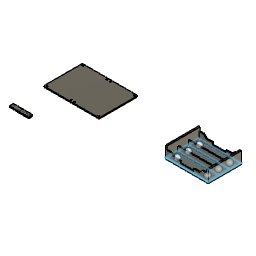
CellSyncLib (Autodesk Fusion 360 design; units mm, degrees)
Autodesk Fusion 360 part; units mm, degrees
sketch "Sketch1" plane through (0, 0, 0) normal (0, 0, 1) x (1, 0, 0)
  line L0 (-200.4, 100) -> (-100, 100)
  line L1 (-100, 100) -> (-100, 30)
  line L2 (-100, 30) -> (-200.4, 30)
  line L3 (-200.4, 30) -> (-200.4, 100)
  circle A0 centre (-197, 33) radius 1.5
  circle A1 centre (-197, 97.5) radius 1.5
  circle A2 centre (-153.5, 97.5) radius 1.5
  circle A3 centre (-153.5, 33) radius 1.5
  circle A4 centre (-147, 33) radius 1.5
  circle A5 centre (-147, 97.5) radius 1.5
  circle A6 centre (-103.5, 33) radius 1.5
  circle A7 centre (-103.5, 97.5) radius 1.5
  dimension "d1" = 100.4
  dimension "d2" = 70
  dimension "d3" = 3
  dimension "d4" = 3
  dimension "d5" = 3.4
  dimension "d6" = 3
  dimension "d7" = 3.4
  dimension "d8" = 64.5
  dimension "d9" = 3
  dimension "d10" = 3
  dimension "d11" = 64.5
  dimension "d12" = 3
  dimension "d13" = 3
  dimension "d14" = 64.5
  dimension "d15" = 3
  dimension "d16" = 3
  dimension "d17" = 64.5
  constraint horizontal L0
  constraint vertical L1
  constraint horizontal L2
  constraint vertical L3
  measures "d1" distance of L0.start L0.end
  measures "d2" distance of L0.start L2.end
  measures "d3" diameter of A0
  measures "d4" distance of L2 A0.centre
  measures "d5" distance of L3 A0.centre
  measures "d6" diameter of A1
  measures "d7" distance of L3 A1.centre
  measures "d8" distance of A0.centre A1.centre
  measures "d9" diameter of A3
  measures "d10" diameter of A2
  measures "d11" distance of A3.centre A2.centre
  measures "d12" diameter of A4
  measures "d13" diameter of A5
  measures "d14" distance of A4.centre A5.centre
  measures "d15" diameter of A6
  measures "d16" diameter of A7
  measures "d17" distance of A6.centre A7.centre
extrude "Extrude1" add sketch "Sketch1" along normal blind 1.6 makes body 1
sketch "Sketch2" plane through (0, 0, 0) normal (0, 0, 1) x (1, 0, 0)
  line L0 (-200, -25) -> (-165, -25)
  line L1 (-165, -25) -> (-165, -32.5)
  line L2 (-165, -32.5) -> (-200, -32.5)
  line L3 (-200, -32.5) -> (-200, -25)
  line L4 (-166, -26) -> (-169, -26)
  line L5 (-169, -26) -> (-169, -31)
  line L6 (-169, -31) -> (-166, -31)
  line L7 (-166, -31) -> (-166, -26)
  line L8 (-172.6, -26) -> (-172.6, -31)
  line L9 (-169.6, -26) -> (-172.6, -26)
  line L10 (-172.6, -31) -> (-169.6, -31)
  line L11 (-169.6, -31) -> (-169.6, -26)
  line L12 (-176.2, -26) -> (-176.2, -31)
  line L13 (-173.2, -26) -> (-176.2, -26)
  line L14 (-176.2, -31) -> (-173.2, -31)
  line L15 (-173.2, -31) -> (-173.2, -26)
  line L16 (-179.8, -26) -> (-179.8, -31)
  line L17 (-176.8, -26) -> (-179.8, -26)
  line L18 (-179.8, -31) -> (-176.8, -31)
  line L19 (-176.8, -31) -> (-176.8, -26)
  line L20 (-183.4, -26) -> (-183.4, -31)
  line L21 (-180.4, -26) -> (-183.4, -26)
  line L22 (-183.4, -31) -> (-180.4, -31)
  line L23 (-180.4, -31) -> (-180.4, -26)
  line L24 (-187, -26) -> (-187, -31)
  line L25 (-184, -26) -> (-187, -26)
  line L26 (-187, -31) -> (-184, -31)
  line L27 (-184, -31) -> (-184, -26)
  line L28 (-197, -27) -> (-195, -27)
  line L29 (-195, -27) -> (-195, -30)
  line L30 (-195, -30) -> (-197, -30)
  line L31 (-197, -30) -> (-197, -27)
  dimension "d20" = 35
  dimension "d21" = 7.5
  dimension "d24" = -18
  dimension "d25" = 0
  constraint horizontal L0
  constraint vertical L1
  constraint horizontal L2
  constraint vertical L3
  constraint horizontal L4
  constraint vertical L5
  constraint horizontal L6
  constraint vertical L7
  constraint horizontal L28
  constraint vertical L29
  constraint horizontal L30
  constraint vertical L31
  measures "d20" distance of L0.start L0.end
  measures "d21" distance of L0.start L2.end
extrude "Extrude2" add sketch "Sketch2" along normal blind 1.6 separate body contours L0 L1 L2 L3 | L4 L5 L6 L7 | L8 L9 L10 L11 | L12 L13 L14 L15 | L16 L17 L18 L19 | L20 L21 L22 L23 | L24 L25 L26 L27 | L28 L29 L30 L31 makes body 2
extrude "Extrude3" add sketch "Sketch2" against normal blind 2 contours L4 L5 L6 L7 | L8 L9 L10 L11 | L12 L13 L14 L15 | L16 L17 L18 L19 | L20 L21 L22 L23 | L24 L25 L26 L27 | L28 L29 L30 L31 bodies 2
sketch "Sketch3" plane through (0, 0, 0) normal (0, 0, 1) x (1, 0, 0)
  line L0 (20, 90) -> (97.4, 90)
  line L1 (97.4, 90) -> (97.4, 30)
  line L2 (97.4, 30) -> (20, 30)
  line L3 (20, 30) -> (20, 90)
  line L4 (94.7, 90) -> (94.7, 30)
  line L5 (22.7, 90) -> (22.7, 30)
  line L6 (22.7, 88.3) -> (94.7, 88.3)
  line L7 (22.7, 70.4) -> (94.7, 70.4)
  line L8 (22.7, 68.7) -> (94.7, 68.7)
  line L9 (22.7, 51.3) -> (94.7, 51.3)
  line L10 (22.7, 49.6) -> (94.7, 49.6)
  line L11 (22.7, 31.7) -> (94.7, 31.7)
  circle A0 centre (86.2, 80) radius 1.5
  circle A1 centre (86.2, 40) radius 1.5
  circle A2 centre (86.2, 60) radius 1.5
  circle A3 centre (31.2, 80) radius 1.5
  circle A4 centre (31.2, 60) radius 1.5
  circle A5 centre (31.2, 40) radius 1.5
  dimension "d30" = 77.4
  dimension "d31" = 60
  dimension "d32" = 2.7
  dimension "d33" = 2.7
  dimension "d34" = 1.7
  dimension "d35" = 17.9
  dimension "d36" = 1.7
  dimension "d37" = 1.7
  dimension "d38" = 17.9
  dimension "d39" = 1.7
  dimension "d57" = 3
  dimension "d58" = 11.2
  dimension "d59" = 10
  dimension "d60" = 3
  dimension "d61" = 11.2
  dimension "d62" = 10
  dimension "d63" = 3
  dimension "d64" = 11.2
  dimension "d65" = 3
  dimension "d66" = 3
  dimension "d67" = 3
  constraint horizontal L0
  constraint vertical L1
  constraint horizontal L2
  constraint vertical L3
  constraint coincident L0 L4.start
  constraint coincident L2 L4.end
  constraint perpendicular L0 L4
  constraint coincident L0 L5.start
  constraint coincident L2 L5.end
  constraint perpendicular L2 L5
  constraint perpendicular L1 L6
  constraint perpendicular L1 L7
  constraint perpendicular L1 L8
  constraint perpendicular L1 L9
  constraint perpendicular L1 L10
  constraint perpendicular L1 L11
  constraint coincident L5 L6.start
  constraint coincident L5 L7.start
  constraint coincident L5 L8.start
  constraint coincident L5 L9.start
  constraint coincident L5 L10.start
  constraint coincident L5 L11.start
  constraint coincident L4 L11.end
  constraint coincident L4 L10.end
  constraint coincident L4 L9.end
  constraint coincident L4 L8.end
  constraint coincident L4 L7.end
  constraint coincident L4 L6.end
  measures "d30" distance of L0.start L0.end
  measures "d31" distance of L0.start L2.end
  measures "d32" distance of L1 L4
  measures "d33" distance of L3 L5
  measures "d34" distance of L0 L6
  measures "d35" distance of L6 L7
  measures "d36" distance of L7 L8
  measures "d37" distance of L2 L11
  measures "d38" distance of L10 L11
  measures "d39" distance of L9 L10
  measures "d57" diameter of A0
  measures "d58" distance of L1 A0.centre
  measures "d59" distance of L0 A0.centre
  measures "d60" diameter of A1
  measures "d61" distance of L1 A1.centre
  measures "d62" distance of L2 A1.centre
  measures "d63" diameter of A2
  measures "d64" distance of L1 A2.centre
  measures "d65" diameter of A3
  measures "d66" diameter of A5
  measures "d67" diameter of A4
extrude "Extrude4" add sketch "Sketch3" against normal blind 2.5 separate body contours L0 L2 L3 L5 | L0 L4 L5 L6 | L0 L1 L2 L4 | L4 L5 L6 L7 | L2 L4 L5 L11 | L4 L5 L7 L8 | L4 L5 L10 L11 | L4 L5 L8 L9 | L4 L5 L9 L10 | A0 | A1 | A2 | A3 | A4 | A5 makes body 3
extrude "Extrude5" add sketch "Sketch3" along normal blind 19 contours L0 L2 L3 L5 | L0 L1 L2 L4 bodies 3
extrude "Extrude6" add sketch "Sketch3" against normal blind 2 contours L4 L5 L7 L8 | L4 L5 L9 L10 bodies 3
extrude "Extrude7" add sketch "Sketch3" along normal blind 12.5 contours L0 L4 L5 L6 | L2 L4 L5 L11 bodies 3
sketch "Sketch4" plane through (0, 30, 0) normal (0, -1, 0) x (1, 0, 0)
  line L0 (94.7, 12.5) -> (22.7, 12.5)
  line L1 (22.7, 12.5) -> (22.7, 19)
  line L2 (22.7, 19) -> (20, 19)
  line L3 (20, 19) -> (20, -2.5)
  line L4 (20, -2.5) -> (97.4, -2.5)
  line L5 (97.4, -2.5) -> (97.4, 19)
  line L6 (97.4, 19) -> (94.7, 19)
  line L7 (94.7, 19) -> (94.7, 12.5)
  line L8 (22.7, 12.5) -> (30.7, 12.5)
  line L9 (58.7, 12.5) -> (58.7, 25)
  line L10 (22.7, 12.5) -> (22.7, 5)
  line L11 (35.7, 7.5) -> (46.7, 7.5)
  line L12 (30.7, 12.5) -> (35.7, 7.5)
  line L13 (46.7, 7.5) -> (46.7, 3.5)
  line L14 (94.7, 12.5) -> (86.7, 12.5)
  line L15 (86.7, 12.5) -> (81.7, 7.5)
  line L16 (81.7, 7.5) -> (70.7, 7.5)
  line L17 (70.7, 7.5) -> (70.7, 3.5)
  line L18 (46.7, 3.5) -> (70.7, 3.5)
  line L19 (30.7, 12.5) -> (86.7, 12.5)
  point P0 (22.7, 12.5)
  point P1 (94.7, 12.5)
  dimension "d48" = 8
  dimension "d49" = 5
  dimension "d50" = 13
  dimension "d51" = 11
  dimension "d52" = 4
  constraint coincident P0 L0.end
  constraint perpendicular L1 L8
  constraint midpoint L0 L9.start
  constraint perpendicular L0 L9
  constraint perpendicular L0 L10
  constraint parallel L0 L11
  constraint perpendicular L11 L13
  constraint symmetric P0 L9 P1
  constraint symmetric L8.end L9 L14.end
  constraint symmetric L9 L11.start L15.end
  constraint symmetric L9 L11.end L16.end
  constraint symmetric L9 L13.end L17.end
  measures "d48" distance of P0 L8.end
  measures "d49" distance of L8 L11
  measures "d50" distance of L10 L11.start
  measures "d51" distance of L11.start L11.end
  measures "d52" distance of L11.end L13.end
extrude "Extrude8" cut sketch "Sketch4" against normal blind 64 contours L0 L11 L12 L13 L15 L16 L17 L18 L19 bodies 3
extrude "Extrude9" add sketch "Sketch3" along normal blind 9.2 separate body contours L4 L5 L7 L8 | L4 L5 L9 L10 makes body 4 at (46.7, 70.4, 6.1333) makes body 5 at (46.7, 51.3, 6.1333)
combine "Combine1" operation add target body 5 tool bodies 4 3
extrude "Extrude10" cut sketch "Sketch3" against normal blind 15 contours A0 | A1 | A2 | A3 | A4 | A5 bodies 5
copy_body "Body->Comp1" bodies 5 removing the originals makes body 6 in component "CellHolder1S3P"
copy_body "Body->Comp2" bodies 1 removing the originals makes body 7 in component "MainBoard"
copy_body "Body->Comp3" bodies 2 removing the originals makes body 8 in component "BMS1S"
component "CellHolder1S3P" placed x (1, 0, 0) y (0, 1, 0) z (0, 0, 1) at (0, 0, 0)
component "MainBoard" placed x (1, 0, 0) y (0, 1, 0) z (0, 0, 1) at (0, 0, 0)
component "BMS1S" placed x (1, 0, 0) y (0, 1, 0) z (0, 0, 1) at (0, 0, 0)
named bodies: "BMS1S"
